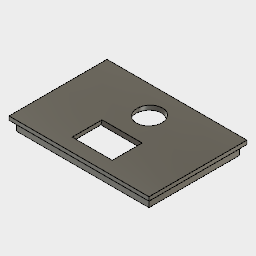
Jenkins_Monitor_Top v1 (Autodesk Fusion 360 design; units mm, degrees)
Autodesk Fusion 360 part; units mm, degrees
sketch "Sketch1" plane through (0, 0, 0) normal (0, 0, 1) x (1, 0, 0)
  line L0 (-69.5, 47.5) -> (69.5, 47.5)
  line L1 (69.5, 47.5) -> (69.5, -47.5)
  line L2 (69.5, -47.5) -> (-69.5, -47.5)
  line L3 (-69.5, -47.5) -> (-69.5, 47.5)
  line L4 (-69.5, 47.5) -> (69.5, -47.5) construction
  line L5 (69.5, 47.5) -> (-69.5, -47.5) construction
  line L6 (-73.5, 51.5) -> (73.5, 51.5)
  line L7 (73.5, 51.5) -> (73.5, -51.5)
  line L8 (73.5, -51.5) -> (-73.5, -51.5)
  line L9 (-73.5, -51.5) -> (-73.5, 51.5)
  line L10 (-73.5, 51.5) -> (73.5, -51.5) construction
  line L11 (73.5, 51.5) -> (-73.5, -51.5) construction
  line L12 (0, -47.5) -> (0, -37.5)
  line L13 (0, -37.5) -> (21, -37.5)
  line L14 (21, -37.5) -> (-21, -37.5)
  line L15 (-21, -37.5) -> (-21, -7.5)
  line L16 (-21, -7.5) -> (21, -7.5)
  line L17 (21, -7.5) -> (21, -37.5)
  line L18 (-67.5, -45.5) -> (67.5, -45.5)
  line L19 (67.5, -45.5) -> (67.5, 45.5)
  line L20 (67.5, 45.5) -> (-67.5, 45.5)
  line L21 (-67.5, 45.5) -> (-67.5, -45.5)
  line L22 (-67.5, -45.5) -> (67.5, 45.5) construction
  line L23 (67.5, -45.5) -> (-67.5, 45.5) construction
  dimension "d1" = 139
  dimension "d2" = 95
  dimension "d3" = 147
  dimension "d4" = 103
  dimension "d5" = 10
  dimension "d6" = 21
  dimension "d7" = 42
  dimension "d8" = 30
  dimension "d13" = 135
  dimension "d14" = 91
  measures "d1" distance of L1.end L2.end
  measures "d2" distance of L0.end L1.end
  measures "d3" distance of L7.end L8.end
  measures "d4" distance of L6.end L7.end
  measures "d5" distance of L12.start L12.end
  measures "d6" distance of L12.end L13.end
  measures "d7" distance of L13.end L14.end
  measures "d8" distance of L13.end L16.end
  measures "d13" distance of L19.end L20.end
  measures "d14" distance of L18.end L19.end
extrude "Extrude1" add sketch "Sketch1" along normal blind 14 contours L0 L1 L2 L3 | L6 L7 L8 L9 | L18 L19 L20 L21
extrude "Extrude2" cut sketch "Sketch1" along normal blind 10 contours L6 L7 L8 L9
extrude "Extrude3" cut sketch "Sketch1" along normal blind 10 contours L18 L19 L20 L21
ref_plane "WorkPlane1" through (0, -7.5, 10) normal (0, -0.951057, 0.309017) x (1, 0, 0)
ref_plane "WorkPlane2" through (0, -37.5, 14) normal (0, -0.951057, 0.309017) x (-1, 0, 0)
sketch "Sketch2" plane through (0, -7.5, 10) normal (0, -0.951057, 0.309017) x (1, 0, 0)
  line L0 (-21, 43.8042) -> (21, 43.8042)
  line L1 (21, 43.8042) -> (21, -36.1958)
  line L2 (21, -36.1958) -> (-21, -36.1958)
  line L3 (-21, -36.1958) -> (-21, 43.8042)
  line L4 (-21, 43.8042) -> (21, -36.1958) construction
  line L5 (21, 43.8042) -> (-21, -36.1958) construction
  line L6 (-21, 3.8042) -> (21, 3.8042)
  point P0 (0, 3.8042)
  dimension "d19" = 42
  dimension "d20" = 80
  measures "d19" distance of L1.end L2.end
  measures "d20" distance of L0.end L1.end
extrude "Extrude4" cut sketch "Sketch2" along normal blind 29.768
sketch "Sketch3" plane through (0, 0, 14) normal (0, 0, 1) x (-1, 0, 0)
  line L0 (73.5, 51.5) -> (-73.5, 51.5)
  line L1 (-73.5, 51.5) -> (-73.5, -51.5)
  line L2 (-73.5, -51.5) -> (73.5, -51.5)
  line L3 (73.5, -51.5) -> (73.5, 51.5)
  line L4 (21, 37.5002) -> (21, 6.2003)
  line L5 (21, 6.2003) -> (-21, 6.2003)
  line L6 (-21, 6.2003) -> (-21, 37.5002)
  line L7 (-21, 37.5002) -> (21, 37.5002)
  line L8 (0, 6.2003) -> (0, -22.6497)
  line L9 (0, -22.6497) -> (10, -22.6497)
  line L10 (0, -22.6497) -> (-10, -22.6497)
  dimension "d23" = 28.85
  dimension "d24" = 10
  dimension "d25" = 10
  measures "d23" distance of L8.start L8.end
  measures "d24" distance of L8.end L9.end
  measures "d25" distance of L8.end L10.end
ref_plane "WorkPlane3" through (5, 22.6497, 14) normal (0, 0.309017, 0.951057) x (1, 0, 0)
sketch "Sketch4" plane through (5, 22.6497, 14) normal (0, 0.309017, 0.951057) x (1, 0, 0)
  circle A0 centre (-5.0302, 0) radius 13
  line L0 (-5, 0) -> (-15, 0)
  dimension "d27" = 26
  measures "d27" diameter of A0
extrude "Extrude5" cut sketch "Sketch4" along normal blind 20 and the other way blind 20
equation "d23 = ( 57.7 / 2 ) * 1 mm"
